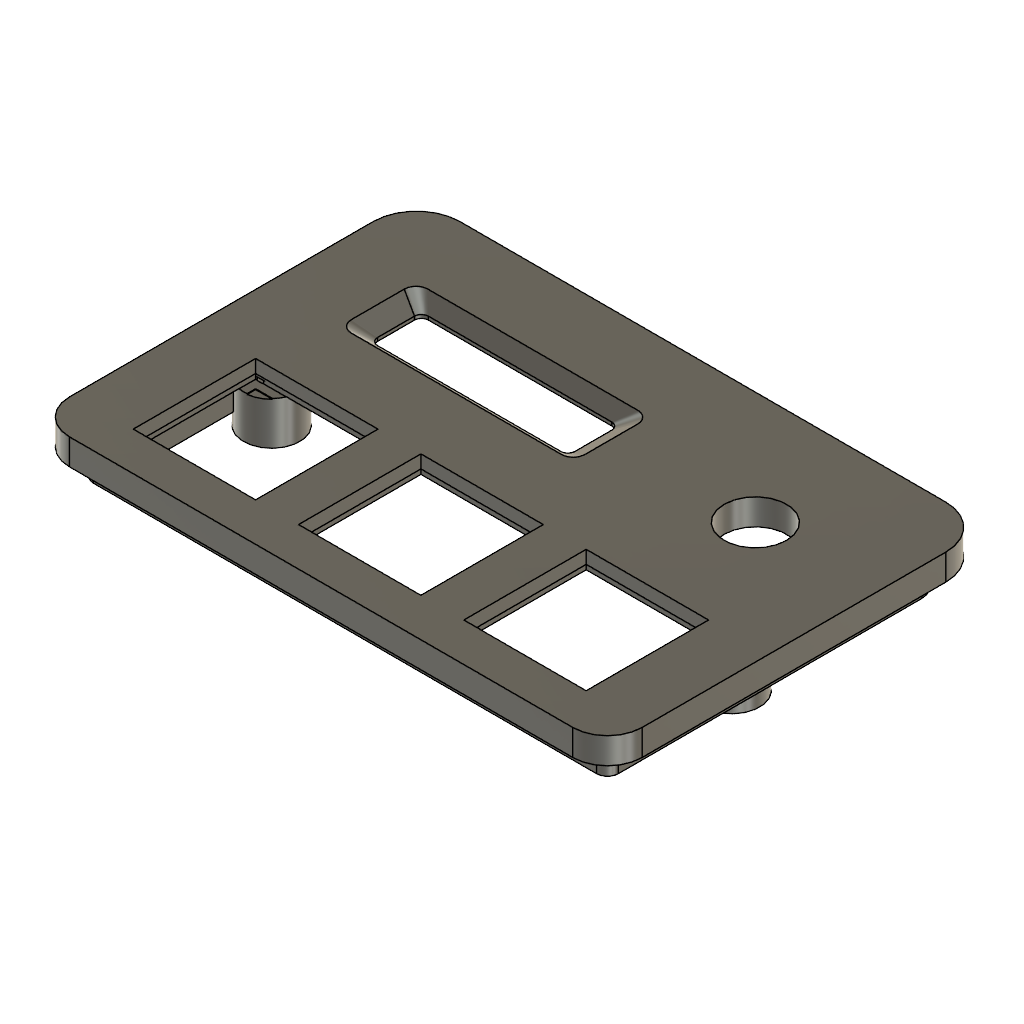
FrontPlate_Small (Autodesk Fusion 360 design; units mm, degrees)
part number: 2026-10-27-18-09-25-359
Autodesk Fusion 360 part; units mm, degrees
sketch "01 - Face outline 66 x 44" plane through (0, 0, 0) normal (0, 0, 1) x (1, 0, 0)
  arc A0 (-33, -18) -> (-29, -22) centre (-29, -18) ccw
  line L0 (-29, -22) -> (29, -22)
  arc A1 (29, -22) -> (33, -18) centre (29, -18) ccw
  line L1 (33, -18) -> (33, 17)
  arc A2 (33, 17) -> (28, 22) centre (28, 17) ccw
  line L2 (28, 22) -> (-28, 22)
  arc A3 (-28, 22) -> (-33, 17) centre (-28, 17) ccw
  line L3 (-33, 17) -> (-33, -18)
extrude "Face - 3 mm" add sketch "01 - Face outline 66 x 44" along normal blind 3
ref_plane "WorkPlane1" through (0, 0, -3) normal (0, 0, 1) x (1, 0, 0)
sketch "02 - Locating skirt" plane through (0, 0, -3) normal (0, 0, 1) x (1, 0, 0)
  arc A0 (-30.25, -18) -> (-29, -19.25) centre (-29, -18) ccw
  line L0 (-29, -19.25) -> (29, -19.25)
  arc A1 (29, -19.25) -> (30.25, -18) centre (29, -18) ccw
  line L1 (30.25, -18) -> (30.25, 17)
  arc A2 (30.25, 17) -> (28, 19.25) centre (28, 17) ccw
  line L2 (28, 19.25) -> (-28, 19.25)
  arc A3 (-28, 19.25) -> (-30.25, 17) centre (-28, 17) ccw
  line L3 (-30.25, 17) -> (-30.25, -18)
  arc A4 (-28.05, -16.25) -> (-27.25, -17.05) centre (-27.25, -16.25) ccw
  line L4 (-27.25, -17.05) -> (27.25, -17.05)
  arc A5 (27.25, -17.05) -> (28.05, -16.25) centre (27.25, -16.25) ccw
  line L5 (28.05, -16.25) -> (28.05, 16.25)
  arc A6 (28.05, 16.25) -> (27.25, 17.05) centre (27.25, 16.25) ccw
  line L6 (27.25, 17.05) -> (-27.25, 17.05)
  arc A7 (-27.25, 17.05) -> (-28.05, 16.25) centre (-27.25, 16.25) ccw
  line L7 (-28.05, 16.25) -> (-28.05, -16.25)
extrude "Locating skirt" add sketch "02 - Locating skirt" along normal blind 3.2
ref_plane "WorkPlane2" through (0, 0, -5) normal (0, 0, 1) x (1, 0, 0)
sketch "03 - M3 bosses" plane through (0, 0, -5) normal (0, 0, 1) x (1, 0, 0)
  circle A0 centre (-26.5, -1.2) radius 3.25
  circle A1 centre (26.5, -1.2) radius 3.25
extrude "Two M3 bosses" add sketch "03 - M3 bosses" along normal blind 5
ref_plane "WorkPlane3" through (0, 0, -0.1) normal (0, 0, 1) x (1, 0, 0)
sketch "04 - OLED pixel window" plane through (0, 0, -0.1) normal (0, 0, 1) x (1, 0, 0)
  arc A0 (-22.37, 6.87) -> (-21.57, 6.07) centre (-21.57, 6.87) ccw
  line L0 (-21.57, 6.07) -> (-0.43, 6.07)
  arc A1 (-0.43, 6.07) -> (0.37, 6.87) centre (-0.43, 6.87) ccw
  line L1 (0.37, 6.87) -> (0.37, 11.13)
  arc A2 (0.37, 11.13) -> (-0.43, 11.93) centre (-0.43, 11.13) ccw
  line L2 (-0.43, 11.93) -> (-21.57, 11.93)
  arc A3 (-21.57, 11.93) -> (-22.37, 11.13) centre (-21.57, 11.13) ccw
  line L3 (-22.37, 11.13) -> (-22.37, 6.87)
extrude "OLED pixel passage" cut sketch "04 - OLED pixel window" along normal blind 2.05
ref_plane "WorkPlane4" through (0, 0, 1.8) normal (0, 0, 1) x (1, 0, 0)
sketch "05a - OLED bezel inner" plane through (0, 0, 1.8) normal (0, 0, 1) x (1, 0, 0)
  arc A0 (-22.37, 6.87) -> (-21.57, 6.07) centre (-21.57, 6.87) ccw
  line L0 (-21.57, 6.07) -> (-0.43, 6.07)
  arc A1 (-0.43, 6.07) -> (0.37, 6.87) centre (-0.43, 6.87) ccw
  line L1 (0.37, 6.87) -> (0.37, 11.13)
  arc A2 (0.37, 11.13) -> (-0.43, 11.93) centre (-0.43, 11.13) ccw
  line L2 (-0.43, 11.93) -> (-21.57, 11.93)
  arc A3 (-21.57, 11.93) -> (-22.37, 11.13) centre (-21.57, 11.13) ccw
  line L3 (-22.37, 11.13) -> (-22.37, 6.87)
ref_plane "WorkPlane5" through (0, 0, 3.08) normal (0, 0, 1) x (1, 0, 0)
sketch "05b - OLED bezel outer" plane through (0, 0, 3.08) normal (0, 0, 1) x (1, 0, 0)
  arc A0 (-24.6, 5.9) -> (-23.2, 4.5) centre (-23.2, 5.9) ccw
  line L0 (-23.2, 4.5) -> (1.2, 4.5)
  arc A1 (1.2, 4.5) -> (2.6, 5.9) centre (1.2, 5.9) ccw
  line L1 (2.6, 5.9) -> (2.6, 12.1)
  arc A2 (2.6, 12.1) -> (1.2, 13.5) centre (1.2, 12.1) ccw
  line L2 (1.2, 13.5) -> (-23.2, 13.5)
  arc A3 (-23.2, 13.5) -> (-24.6, 12.1) centre (-23.2, 12.1) ccw
  line L3 (-24.6, 12.1) -> (-24.6, 5.9)
loft "Recessed OLED bezel" cut profiles "05a - OLED bezel inner", "05b - OLED bezel outer" section 1 section 2
ref_plane "WorkPlane6" through (0, 0, -3.27) normal (0, 0, 1) x (1, 0, 0)
sketch "06 - OLED PCB pocket and insertion channel" plane through (0, 0, -3.27) normal (0, 0, 1) x (1, 0, 0)
  line L0 (-30.8, 2.2) -> (8.8, 2.2)
  line L1 (8.8, 2.2) -> (8.8, 15.8)
  line L2 (8.8, 15.8) -> (-30.8, 15.8)
  line L3 (-30.8, 15.8) -> (-30.8, 2.2)
extrude "OLED pocket - through skirt" cut sketch "06 - OLED PCB pocket and insertion channel" along normal blind 4.67
sketch "07 - Three MX apertures" plane through (0, 0, -0.1) normal (0, 0, 1) x (1, 0, 0)
  line L0 (-26.1, -17.55) -> (-12, -17.55)
  line L1 (-12, -17.55) -> (-12, -3.45)
  line L2 (-12, -3.45) -> (-26.1, -3.45)
  line L3 (-26.1, -3.45) -> (-26.1, -17.55)
  line L4 (-7.05, -17.55) -> (7.05, -17.55)
  line L5 (7.05, -17.55) -> (7.05, -3.45)
  line L6 (7.05, -3.45) -> (-7.05, -3.45)
  line L7 (-7.05, -3.45) -> (-7.05, -17.55)
  line L8 (12, -17.55) -> (26.1, -17.55)
  line L9 (26.1, -17.55) -> (26.1, -3.45)
  line L10 (26.1, -3.45) -> (12, -3.45)
  line L11 (12, -3.45) -> (12, -17.55)
extrude "Three MX switch openings" cut sketch "07 - Three MX apertures" along normal blind 3.2
ref_plane "WorkPlane7" through (0, 0, -0.02) normal (0, 0, 1) x (1, 0, 0)
sketch "08 - MX clip relief" plane through (0, 0, -0.02) normal (0, 0, 1) x (1, 0, 0)
  line L0 (-27.05, -18.5) -> (-11.05, -18.5)
  line L1 (-11.05, -18.5) -> (-11.05, -2.5)
  line L2 (-11.05, -2.5) -> (-27.05, -2.5)
  line L3 (-27.05, -2.5) -> (-27.05, -18.5)
  line L4 (-8, -18.5) -> (8, -18.5)
  line L5 (8, -18.5) -> (8, -2.5)
  line L6 (8, -2.5) -> (-8, -2.5)
  line L7 (-8, -2.5) -> (-8, -18.5)
  line L8 (11.05, -18.5) -> (27.05, -18.5)
  line L9 (27.05, -18.5) -> (27.05, -2.5)
  line L10 (27.05, -2.5) -> (11.05, -2.5)
  line L11 (11.05, -2.5) -> (11.05, -18.5)
extrude "MX relief - leaves 1.5 mm plate" cut sketch "08 - MX clip relief" along normal blind 1.52
sketch "09 - Encoder" plane through (0, 0, -0.1) normal (0, 0, 1) x (1, 0, 0)
  circle A0 centre (19.05, 9) radius 3.6
extrude "EC11 bushing clearance" cut sketch "09 - Encoder" along normal blind 3.2
ref_plane "WorkPlane8" through (0, 0, -5.2) normal (0, 0, 1) x (1, 0, 0)
sketch "10 - M3 pilot holes" plane through (0, 0, -5.2) normal (0, 0, 1) x (1, 0, 0)
  circle A0 centre (-26.5, -1.2) radius 1.35
  circle A1 centre (26.5, -1.2) radius 1.35
extrude "M3 blind pilots" cut sketch "10 - M3 pilot holes" along normal blind 5.5
named bodies: "small front plate"
